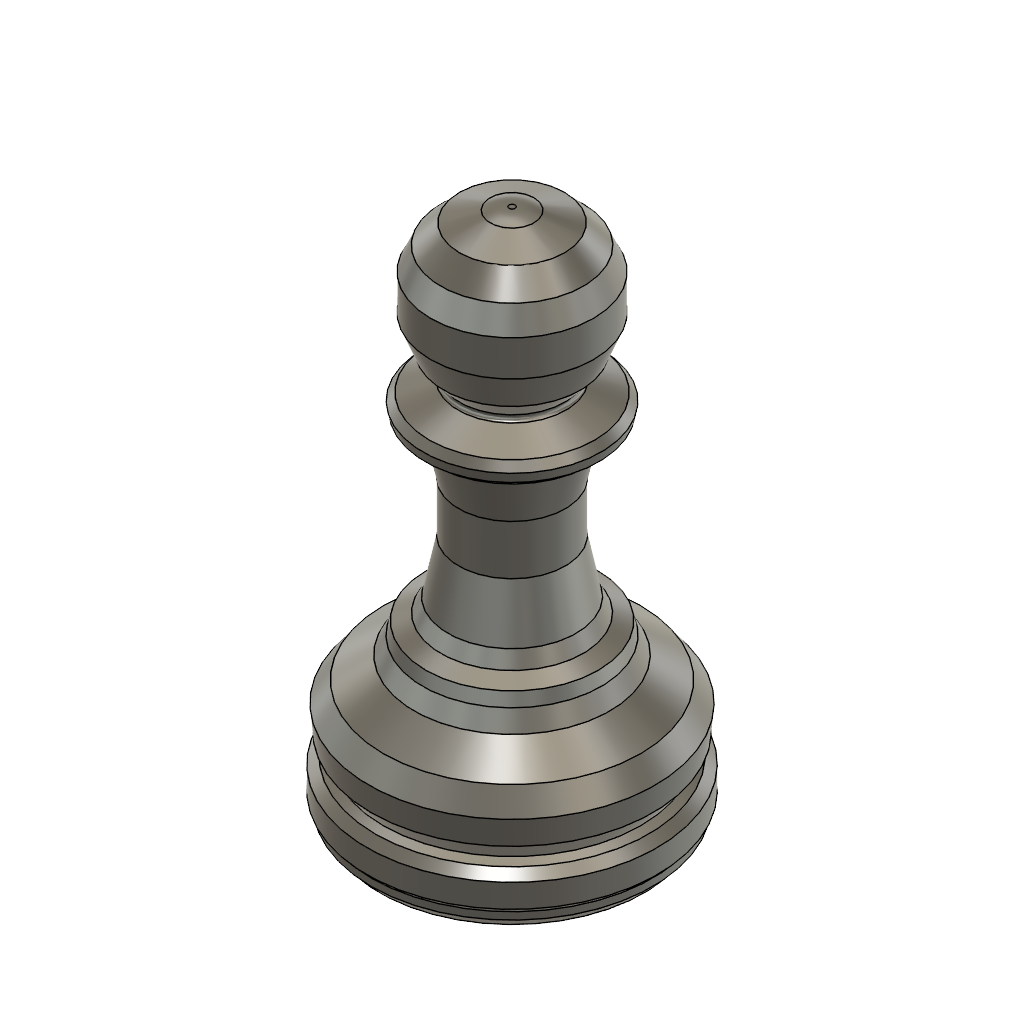
Board Assembly (Autodesk Fusion 360 archive; units mm, degrees)
design "Simple Pawn"
part number: 2026-10-13-13-34-46-267
Autodesk Fusion 360 part; units mm, degrees
sketch "Sketch1" plane through (0, 0, 0) normal (1, 0, 0) x (0, 0, -1)
  line L0 (-0.0053, -17.729) -> (1.2282, -17.729)
  line L1 (1.2282, -17.729) -> (5, -17.5)
  line L2 (5, -17.5) -> (7.3961, -17.1698)
  line L3 (7.3961, -17.1698) -> (8.684, -16.9923)
  line L4 (8.684, -16.9923) -> (9.2382, -16.3474)
  line L5 (9.2382, -16.3474) -> (9.2382, -15.8704)
  line L6 (9.2382, -15.8704) -> (9.5278, -15.5336)
  line L7 (9.5278, -15.5336) -> (9.5278, -14)
  line L8 (9.5278, -14) -> (8.9611, -13.5131)
  line L9 (8.9611, -13.5131) -> (8.4323, -13.3046)
  line L10 (8.4323, -13.3046) -> (9.2444, -12.1533)
  line L11 (9.2444, -12.1533) -> (9.383, -10.525)
  line L12 (9.383, -10.525) -> (8.4323, -9.2091)
  line L13 (8.4323, -9.2091) -> (7.1598, -8.3116)
  line L14 (7.1598, -8.3116) -> (6.4164, -7.7872)
  line L15 (6.4164, -7.7872) -> (5.85, -6.6762)
  line L16 (5.85, -6.6762) -> (5.6527, -5.8538)
  line L17 (5.6527, -5.8538) -> (4.6658, -5.3933)
  line L18 (4.6658, -5.3933) -> (4.2015, -4.4825)
  line L19 (4.2015, -4.4825) -> (3.5, -1)
  line L20 (3.5, -1) -> (3.5, 2.2549)
  line L21 (3.5, 2.2549) -> (4.2015, 5.5608)
  line L22 (4.2015, 5.5608) -> (5.1592, 5.5608)
  line L23 (5.1592, 5.5608) -> (5.7184, 6.0378)
  line L24 (5.7184, 6.0378) -> (5.8486, 6.6512)
  line L25 (5.8486, 6.6512) -> (5.4388, 7.1316)
  line L26 (5.4388, 7.1316) -> (4.5, 7.5)
  line L27 (4.5, 7.5) -> (3.7306, 7.8019)
  line L28 (3.7306, 7.8019) -> (3.2099, 8.0063)
  line L29 (3.2099, 8.0063) -> (4.5, 9.5)
  line L30 (4.5, 9.5) -> (5.3466, 11.6575)
  line L31 (5.3466, 11.6575) -> (5.3466, 14)
  line L32 (5.3466, 14) -> (4.6822, 15.4952)
  line L33 (4.6822, 15.4952) -> (3.4487, 16.7781)
  line L34 (3.4487, 16.7781) -> (0.8335, 17.6828)
  line L35 (0.8335, 17.6828) -> (0, 17.6828)
  line L36 (-0.0053, -17.729) -> (0, 17.6828)
  constraint horizontal L0
  constraint parallel L2 L3
  constraint vertical L5
  constraint parallel L4 L6
  constraint parallel L5 L7
  constraint perpendicular L6 L8
  constraint perpendicular L10 L13
  constraint perpendicular L10 L14
  constraint parallel L15 L18
  constraint vertical L20
  constraint perpendicular L20 L22
  constraint parallel L21 L24
  constraint perpendicular L23 L25
  constraint parallel L26 L27
  constraint perpendicular L28 L30
  constraint vertical L31
  constraint horizontal L35
revolve "Revolve1" add sketch "Sketch1" angle 360 about axis through (0, -17.729, 0.0053) along (0, 1, -0.000151)
move_body "Move1" bodies 1 to x (1, 0, 0) y (0, 1, 0) z (0, 0, 1) at (0, 0, -28)
sketch "Sketch2" plane through (0, 0, 0) normal (0, 0, 1) x (1, 0, 0)
  line L0 (-8.7, -17) -> (8.5, -17)
  line L1 (8.5, -17) -> (8.5, -18)
  line L2 (8.5, -18) -> (-8.7, -18)
  line L3 (-8.7, -18) -> (-8.7, -17)
  constraint horizontal L0
  constraint vertical L1
  constraint horizontal L2
  constraint vertical L3
extrude "Extrude1" cut sketch "Sketch2" against normal blind 39
fillet "Fillet1" radius 0.25 1 edges at (-2.994, 8.0066, -29.1598)
fillet "Fillet2" radius 3.8 1 edges at (-0.7771, 17.6828, -28.3014)
sketch "Sketch3" plane through (0, -17, 0) normal (0, -1, 0) x (1, 0, 0)
  ellipse E0 centre (0, -28.0042) end of major axis (0, -36.6284) minor radius 8.6242 (8.5, -26.5458) -> (8.5, -29.4626) ccw
  line L0 (8.5, -29.4626) -> (8.5, -26.5458)
  circle A0 centre (0, -28.0042) radius 3.15
  dimension "d8" = 6.3
  constraint concentric E0 A0
  measures "d8" diameter of A0
extrude "Extrude2" cut sketch "Sketch3" against normal blind 2.2 contours A0

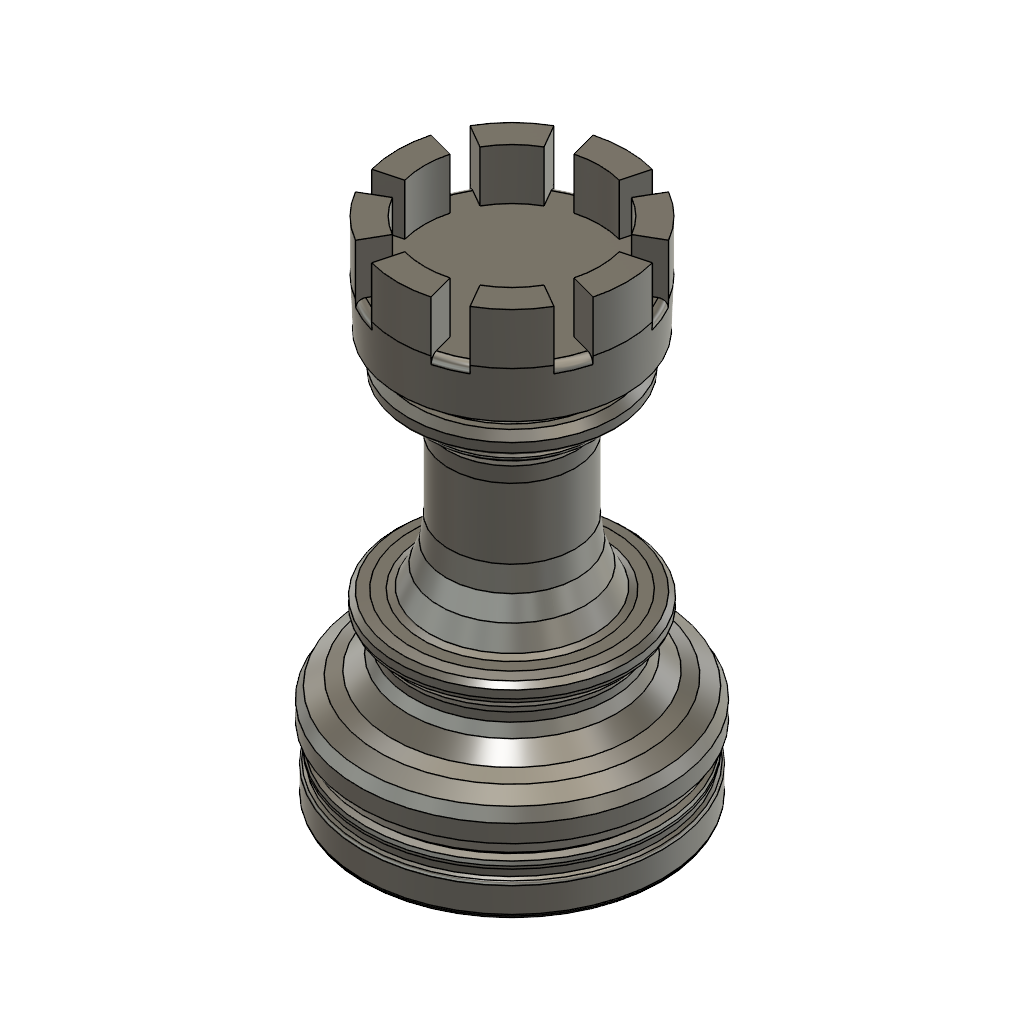
design "Tower"
part number: 2026-10-13-14-45-00-244
Autodesk Fusion 360 part; units mm, degrees
sketch "Sketch1" plane through (0, 0, 0) normal (0, 0, 1) x (1, 0, 0)
  line L0 (0, -18.1) -> (2.1, -18.1)
  line L1 (2.1, -18.1) -> (5.6, -17.9)
  line L2 (5.6, -17.9) -> (8.5, -17.4)
  line L3 (8.5, -17.4) -> (10.2, -16.7)
  line L4 (10.2, -16.7) -> (10.3, -16.5)
  line L5 (10.3, -16.5) -> (10.3, -14.6)
  line L6 (10.3, -14.6) -> (10, -14.4)
  line L7 (10, -14.4) -> (10.15, -13.7818)
  line L8 (10.15, -13.7818) -> (10.075, -13.4284)
  line L9 (10.075, -13.4284) -> (9.6033, -13.3139)
  line L10 (9.6033, -13.3139) -> (9.9799, -12.9804)
  line L11 (9.9799, -12.9804) -> (10.5, -12.1)
  line L12 (10.5, -12.1) -> (10.5, -10.9)
  line L13 (10.5, -10.9) -> (10.1125, -10.1526)
  line L14 (10.1125, -10.1526) -> (9.1034, -9.5566)
  line L15 (9.1034, -9.5566) -> (8.2, -9.2)
  line L16 (8.2, -9.2) -> (7.6575, -8.7025)
  line L17 (7.6575, -8.7025) -> (7.1474, -8.2346)
  line L18 (7.1474, -8.2346) -> (6.8, -7.5)
  line L19 (6.8, -7.5) -> (6.8, -6.9)
  line L20 (6.8, -6.9) -> (7.1474, -6.3425)
  line L21 (7.1474, -6.3425) -> (7.8026, -5.6281)
  line L22 (7.8026, -5.6281) -> (7.9288, -5.3339)
  line L23 (7.9288, -5.3339) -> (7.9288, -4.8)
  line L24 (7.9288, -4.8) -> (7.5936, -4.4926)
  line L25 (7.5936, -4.4926) -> (6.9, -4.4)
  line L26 (6.9, -4.4) -> (6.1, -4.4)
  line L27 (6.1, -4.4) -> (5.6617, -4.2347)
  line L28 (5.6617, -4.2347) -> (5, -2.9)
  line L29 (5, -2.9) -> (4.5, -1.5)
  line L30 (4.5, -1.5) -> (4.3, 0.1)
  line L31 (4.3, 0.1) -> (4.3, 2.7)
  line L32 (4.3, 2.7) -> (4.3, 4.9)
  line L33 (4.3, 4.9) -> (4.4, 6)
  line L34 (4.4, 6) -> (5.1, 6.8)
  line L35 (5.1, 6.8) -> (5.6, 7.2)
  line L36 (5.6, 7.2) -> (5.4101, 7.4374)
  line L37 (5.4101, 7.4374) -> (5.4101, 7.8)
  line L38 (5.4101, 7.8) -> (6.4, 8.4)
  line L39 (6.4, 8.4) -> (7, 8.4)
  line L40 (7, 8.4) -> (7.1, 9.3)
  line L41 (7.1, 9.3) -> (6.7, 9.8)
  line L42 (0, 9.9896) -> (0, -18.1)
  line L43 (6.7, 9.8) -> (6.2466, 9.8)
  line L44 (6.2466, 9.8) -> (7.5109, 10.8114)
  line L45 (7.5109, 10.8114) -> (7.7356, 10.9912)
  line L46 (7.7356, 10.9912) -> (7.8539, 14.2278)
  line L47 (7.8539, 14.2278) -> (0, 14.2278)
  line L48 (0, 14.2278) -> (0, 9.9896)
  constraint horizontal L0
  constraint vertical L5
  constraint perpendicular L7 L9
  constraint vertical L12
  constraint perpendicular L11 L14
  constraint parallel L16 L17
  constraint vertical L19
  constraint perpendicular L16 L21
  constraint parallel L19 L23
  constraint perpendicular L21 L24
  constraint perpendicular L23 L26
  constraint vertical L31
  constraint parallel L31 L32
  constraint vertical L37
  constraint horizontal L39
  constraint perpendicular L0 L42
  constraint horizontal L43
  constraint perpendicular L41 L44
  constraint perpendicular L41 L45
  constraint horizontal L47
  constraint perpendicular L47 L48
revolve "Revolve1" add sketch "Sketch1" angle 360 about axis through (0, 9.9896, 0) along (0, -1, 0)
sketch "Sketch2" plane through (0, 14.2278, 0) normal (0, 1, 0) x (-1, 0, 0)
  circle A0 centre (0, 0) radius 7.8539
  circle A1 centre (0, 0) radius 6
  line L0 (0, 0) -> (-2.0327, -7.5863)
  line L1 (0, 0) -> (2.0327, -7.5863)
  line L2 (0, 0) -> (0, -5.5)
  line L3 (0, -5.5) -> (0, -6)
  line L4 (0, 0) -> (3.927, -6.8017)
  line L5 (0, 0) -> (6.8017, -3.927)
  line L6 (0, 0) -> (7.5863, -2.0327)
  line L7 (0, 0) -> (7.5863, 2.0327)
  line L8 (0, 0) -> (6.8017, 3.927)
  line L9 (0, 0) -> (3.927, 6.8017)
  line L10 (0, 0) -> (2.0327, 7.5863)
  line L11 (0, 0) -> (-2.0327, 7.5863)
  line L12 (0, 0) -> (-3.927, 6.8017)
  line L13 (0, 0) -> (-6.8017, 3.927)
  line L14 (0, 0) -> (-7.5863, 2.0327)
  line L15 (0, 0) -> (-7.5863, -2.0327)
  line L16 (0, 0) -> (-6.8017, -3.927)
  line L17 (0, 0) -> (-3.927, -6.8017)
  dimension "d2" = 12
  dimension "d4" = 15
  dimension "d5" = 15
  dimension "d7" = 360
  constraint concentric A0 A1
  constraint coincident A0.centre A1.centre
  constraint coincident A0 L0.end
  constraint coincident A0 L1.end
  constraint vertical L2
  constraint coincident A1 L3.end
  constraint perpendicular A1 L3
  measures "d2" diameter of A1
  measures "d4" angle of L0 L3
  measures "d5" angle of L1 L2
extrude "Extrude1" add sketch "Sketch2" along normal blind 3.5 contours A0 A1 L6 L7 | A0 A1 L8 L9 | A0 A1 L4 L5 | A0 A1 L10 L11 | A0 A1 L0 L1 | A0 A1 L12 L13 | A0 A1 L14 L15 | A0 A1 L16 L17
fillet "Fillet1" radius 0.5 tangency weight 0.99014 8 edges at (-3.0056, 14.2278, 7.2561) (-7.2561, 14.2278, 3.0056) (-7.2561, 14.2278, -3.0056) (-3.0056, 14.2278, -7.2561) (3.0056, 14.2278, -7.2561) (7.2561, 14.2278, -3.0056) (7.2561, 14.2278, 3.0056) (3.0056, 14.2278, 7.2561)
fillet "Fillet2" radius 0.1 1 edges at (-5.221, 7.2, -2.025)
fillet "Fillet3" radius 0.25 1 edges at (-6.5263, 8.4, -2.5313)
fillet "Fillet4" radius 0.25 2 edges at (-9.603, -16.5, -3.7246) (-9.603, -14.6, -3.7246)
fillet "Fillet5" radius 0.4 1 edges at (-9.4631, -13.7818, -3.6704)
sketch "Sketch3" plane through (0, 0, 0) normal (0, 0, 1) x (1, 0, 0)
  line L0 (-8.5, -17.4) -> (9.5169, -17.4)
  line L1 (9.5169, -17.4) -> (9.5169, -18.8567)
  line L2 (9.5169, -18.8567) -> (-8.5, -18.8567)
  line L3 (-8.5, -18.8567) -> (-8.5, -17.4)
  constraint horizontal L0
  constraint vertical L1
  constraint horizontal L2
  constraint vertical L3
extrude "Extrude2" cut sketch "Sketch3" along normal blind 19 and the other way blind 40.5
scale "Scale1" factors (1.1, 1.1, 1.1) about (4.3, 0.1, 0) bodies 1
sketch "Sketch4" plane through (0, -19.15, 0) normal (0, -1, 0) x (1, 0, 0)
  circle A0 centre (-0.43, 0) radius 9.35
  circle A1 centre (-0.43, 0) radius 3.15
  dimension "d27" = 6.3
  constraint concentric A0 A1
  measures "d27" diameter of A1
extrude "Extrude3" cut sketch "Sketch4" against normal blind 2.2 contours A1

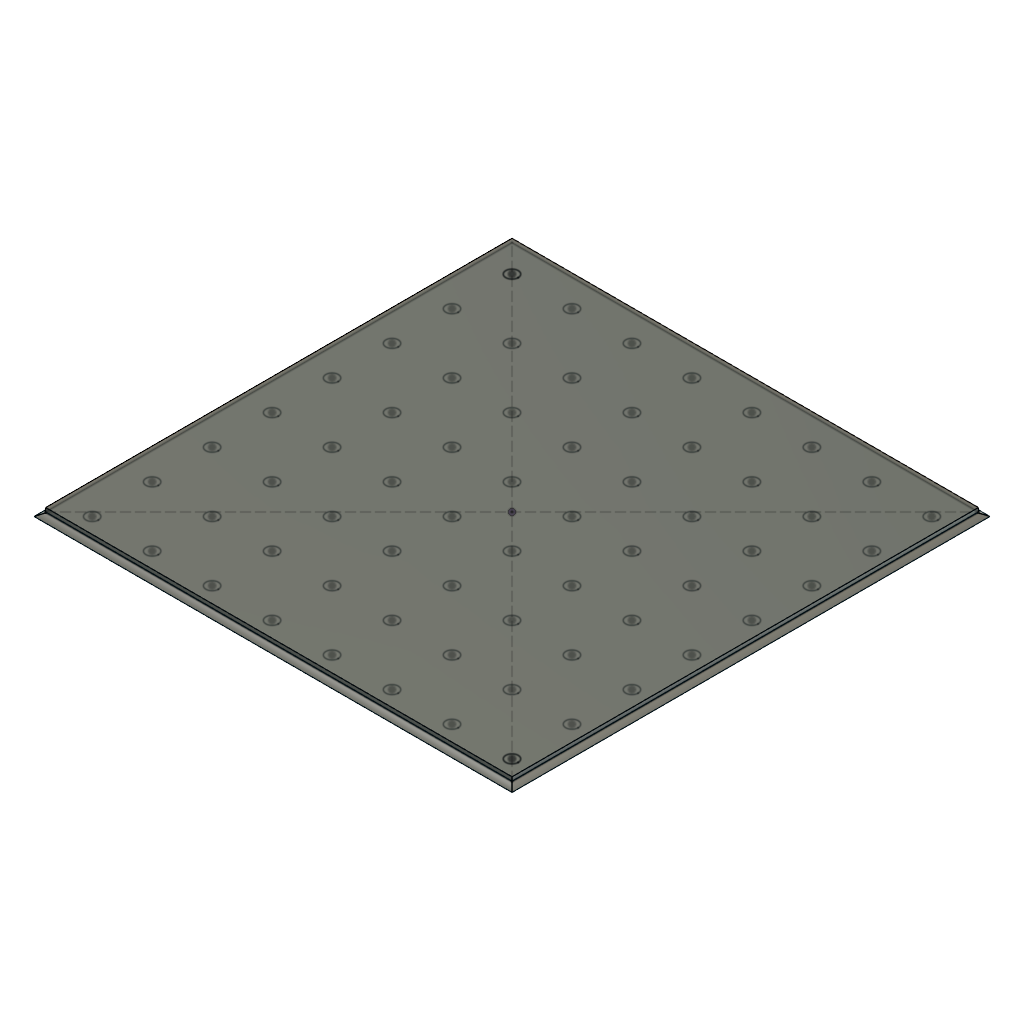
design "Board"
part number: 2026-10-15-21-07-23-463
part number: 2026-10-15-21-11-25-391
Autodesk Fusion 360 part; units mm, degrees
sketch "Sketch1" plane through (0, 0, 0) normal (0, 1, 0) x (1, 0, 0)
  line L0 (120, -120) -> (-120, -120)
  line L1 (-120, -120) -> (-120, 120)
  line L2 (-120, 120) -> (120, 120)
  line L3 (120, 120) -> (120, -120)
  line L4 (120, -120) -> (-120, 120) construction
  line L5 (-120, -120) -> (120, 120) construction
  dimension "d1" = 240
  dimension "d2" = 240
  constraint horizontal L0
  constraint perpendicular L0 L1
  constraint parallel L0 L2
  constraint parallel L1 L3
  constraint coincident L4 origin
  constraint coincident L5 origin
  measures "d1" distance of L1.end L2.end
  measures "d2" distance of L0.end L1.end
extrude "Extrude2" add sketch "Sketch1" along normal blind 2 makes body 1
sketch "Sketch2" plane through (0, 0, 0) normal (0, -1, 0) x (1, 0, 0)
  line L0 (-120, -120) -> (120, -120) construction
  line L1 (120, -120) -> (120, 120) construction
  line L2 (120, 120) -> (-120, 120) construction
  line L3 (-120, 120) -> (-120, -120) construction
  line L4 (-123, 123) -> (-123, -123)
  line L5 (-123, -123) -> (123, -123)
  line L6 (123, -123) -> (123, 123)
  line L7 (123, 123) -> (-123, 123)
  dimension "d5" = 3
extrude "Extrude2'" add sketch "Sketch2" along normal blind 2 makes body 2 in component "Component"
fillet "Fillet1" radius 10 4 edges at (0, 0, 123) (-123, 0, 0) (0, 0, -123) (123, 0, 0) on bodies 2 in component "Component"
sketch "Sketch3" plane through (0, -2, 0) normal (0, -1, 0) x (1, 0, 0)
  line L0 (123, 123) -> (-123, 123)
  line L1 (-123, 123) -> (-123, -123)
  line L2 (-123, -123) -> (123, -123)
  line L3 (123, -123) -> (123, 123)
  circle A0 centre (-108, 108) radius 3.15
  circle A1 centre (108, 108) radius 3.15
  circle A2 centre (-108, -108) radius 3.15
  circle A3 centre (-77.1429, 108) radius 3.15
  circle A4 centre (-46.2857, 108) radius 3.15
  circle A5 centre (-15.4286, 108) radius 3.15
  circle A6 centre (15.4286, 108) radius 3.15
  circle A7 centre (46.2857, 108) radius 3.15
  circle A8 centre (77.1429, 108) radius 3.15
  circle A9 centre (108, 108) radius 3.15
  circle A10 centre (-108, 77.1429) radius 3.15
  circle A11 centre (-77.1429, 77.1429) radius 3.15
  circle A12 centre (-46.2857, 77.1429) radius 3.15
  circle A13 centre (-15.4286, 77.1429) radius 3.15
  circle A14 centre (15.4286, 77.1429) radius 3.15
  circle A15 centre (46.2857, 77.1429) radius 3.15
  circle A16 centre (77.1429, 77.1429) radius 3.15
  circle A17 centre (108, 77.1429) radius 3.15
  circle A18 centre (-108, 46.2857) radius 3.15
  circle A19 centre (-77.1429, 46.2857) radius 3.15
  circle A20 centre (-46.2857, 46.2857) radius 3.15
  circle A21 centre (-15.4286, 46.2857) radius 3.15
  circle A22 centre (15.4286, 46.2857) radius 3.15
  circle A23 centre (46.2857, 46.2857) radius 3.15
  circle A24 centre (77.1429, 46.2857) radius 3.15
  circle A25 centre (108, 46.2857) radius 3.15
  circle A26 centre (-108, 15.4286) radius 3.15
  circle A27 centre (-77.1429, 15.4286) radius 3.15
  circle A28 centre (-46.2857, 15.4286) radius 3.15
  circle A29 centre (-15.4286, 15.4286) radius 3.15
  circle A30 centre (15.4286, 15.4286) radius 3.15
  circle A31 centre (46.2857, 15.4286) radius 3.15
  circle A32 centre (77.1429, 15.4286) radius 3.15
  circle A33 centre (108, 15.4286) radius 3.15
  circle A34 centre (-108, -15.4286) radius 3.15
  circle A35 centre (-77.1429, -15.4286) radius 3.15
  circle A36 centre (-46.2857, -15.4286) radius 3.15
  circle A37 centre (-15.4286, -15.4286) radius 3.15
  circle A38 centre (15.4286, -15.4286) radius 3.15
  circle A39 centre (46.2857, -15.4286) radius 3.15
  circle A40 centre (77.1429, -15.4286) radius 3.15
  circle A41 centre (108, -15.4286) radius 3.15
  circle A42 centre (-108, -46.2857) radius 3.15
  circle A43 centre (-77.1429, -46.2857) radius 3.15
  circle A44 centre (-46.2857, -46.2857) radius 3.15
  circle A45 centre (-15.4286, -46.2857) radius 3.15
  circle A46 centre (15.4286, -46.2857) radius 3.15
  circle A47 centre (46.2857, -46.2857) radius 3.15
  circle A48 centre (77.1429, -46.2857) radius 3.15
  circle A49 centre (108, -46.2857) radius 3.15
  circle A50 centre (-108, -77.1429) radius 3.15
  circle A51 centre (-77.1429, -77.1429) radius 3.15
  circle A52 centre (-46.2857, -77.1429) radius 3.15
  circle A53 centre (-15.4286, -77.1429) radius 3.15
  circle A54 centre (15.4286, -77.1429) radius 3.15
  circle A55 centre (46.2857, -77.1429) radius 3.15
  circle A56 centre (77.1429, -77.1429) radius 3.15
  circle A57 centre (108, -77.1429) radius 3.15
  circle A58 centre (-108, -108) radius 3.15
  circle A59 centre (-77.1429, -108) radius 3.15
  circle A60 centre (-46.2857, -108) radius 3.15
  circle A61 centre (-15.4286, -108) radius 3.15
  circle A62 centre (15.4286, -108) radius 3.15
  circle A63 centre (46.2857, -108) radius 3.15
  circle A64 centre (77.1429, -108) radius 3.15
  circle A65 centre (108, -108) radius 3.15
  dimension "d10" = 6.3
  dimension "d13" = 15
  dimension "d14" = 15
  dimension "d15" = 6.3
  dimension "d16" = 15
  dimension "d17" = 15
  dimension "d18" = 6.3
  dimension "d19" = 15
  dimension "d20" = 15
  dimension "d23" = 216
  dimension "d24" = -216
  measures "d10" diameter of A0
  measures "d13" distance of L1 A0.centre
  measures "d14" distance of L0 A0.centre
  measures "d15" diameter of A1
  measures "d16" distance of L3 A1.centre
  measures "d17" distance of L0 A1.centre
  measures "d18" diameter of A2
  measures "d19" distance of L2 A2.centre
  measures "d20" distance of L1 A2.centre
extrude "Extrude3" cut sketch "Sketch3" against normal blind 2.2 contours A0 bodies 2 in component "Component"
extrude "Extrude4" cut sketch "Sketch3" against normal blind 2.2 contours A0 | A1 A9 | A3 | A4 | A5 | A6 | A7 | A8 bodies 2 in component "Component"
extrude "Extrude5" cut sketch "Sketch3" against normal blind 2.2 contours A10 | A11 | A12 | A13 | A14 | A15 | A16 | A17 bodies 2 in component "Component"
extrude "Extrude6" cut sketch "Sketch3" against normal blind 2.2 contours A18 | A19 | A20 | A21 | A22 | A23 | A24 | A25 bodies 2 in component "Component"
extrude "Extrude7" cut sketch "Sketch3" against normal blind 2.2 contours A26 | A27 | A28 | A29 | A30 | A31 | A32 | A33 bodies 2 in component "Component"
extrude "Extrude8" cut sketch "Sketch3" against normal blind 2.2 contours A34 | A35 | A36 | A37 | A38 | A39 | A40 | A41 bodies 2 in component "Component"
extrude "Extrude9" cut sketch "Sketch3" against normal blind 2.2 contours A42 | A43 | A44 | A45 | A46 | A47 | A48 | A49 bodies 2 in component "Component"
extrude "Extrude10" cut sketch "Sketch3" against normal blind 2.2 contours A50 | A51 | A52 | A53 | A54 | A55 | A56 | A57 bodies 2 in component "Component"
extrude "Extrude3'" cut sketch "Sketch3" against normal blind 2.2 contours A2 A58 | A59 | A60 | A61 | A62 | A63 | A64 | A65 bodies 1
extrude "Extrude12" cut sketch "Sketch3" against normal blind 2.2 contours A2 A58 | A59 | A60 | A61 | A62 | A63 | A64 | A65 bodies 2 in component "Component"
extrude "Extrude11" [rolled back] along distance -2.2 taper angle 0 in component "Component"
component "Component" placed x (1, 0, 0) y (0, 1, 0) z (0, 0, 1) at (0, 0, 0)

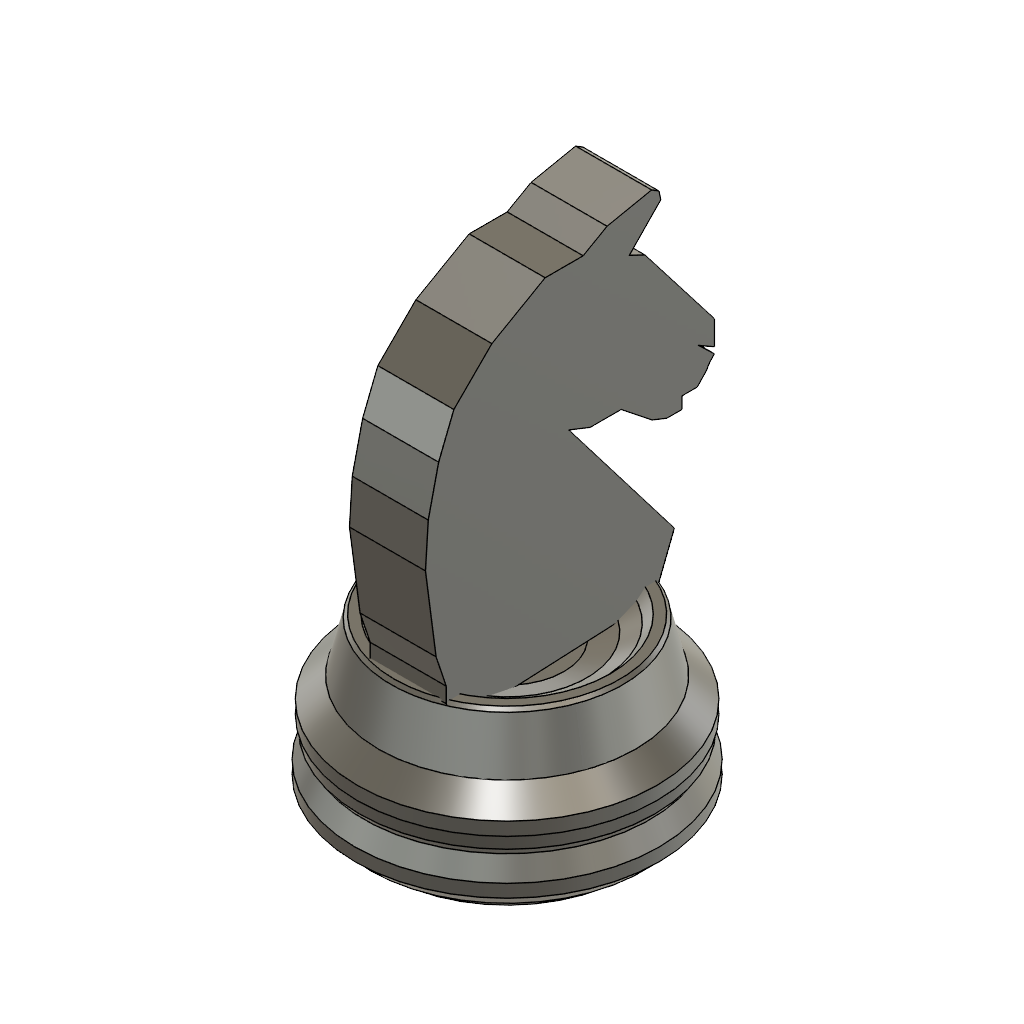
design "Horse"
part number: 2026-10-14-15-19-01-770
Autodesk Fusion 360 part; units mm, degrees
sketch "Sketch1" plane through (0, 0, 0) normal (1, 0, 0) x (0, 0, -1)
  line L0 (0, -17.5) -> (2.7905, -17.1997)
  line L1 (2.7905, -17.1997) -> (5.5, -16.5)
  line L2 (5.5, -16.5) -> (7.9291, -15.3606)
  line L3 (7.9291, -15.3606) -> (9, -14.5)
  line L4 (9, -14.5) -> (10, -13.5)
  line L5 (10, -13.5) -> (10, -12.6561)
  line L6 (10, -12.6561) -> (9.7013, -12.0194)
  line L7 (9.7013, -12.0194) -> (9.4046, -11.3868)
  line L8 (9.4046, -11.3868) -> (9.7013, -10.9252)
  line L9 (9.7013, -10.9252) -> (9.8507, -10.0868)
  line L10 (9.8507, -10.0868) -> (9.8507, -9.2214)
  line L11 (9.8507, -9.2214) -> (9.2003, -8.5993)
  line L12 (9.2003, -8.5993) -> (8.4409, -7.8731)
  line L13 (8.4409, -7.8731) -> (8.2672, -7.1795)
  line L14 (8.2672, -7.1795) -> (8.0608, -6.3555)
  line L15 (8.0608, -6.3555) -> (7.8831, -5.646)
  line L16 (7.8831, -5.646) -> (7.6911, -4.8793)
  line L17 (7.6911, -4.8793) -> (7.6218, -4.6025)
  line L18 (7.6218, -4.6025) -> (7.4153, -4.3938)
  line L19 (7.4153, -4.3938) -> (6.7932, -4.3938)
  line L20 (6.7932, -4.3938) -> (6.2833, -4.8985)
  line L21 (6.2833, -4.8985) -> (5.2381, -5.408)
  line L22 (5.2381, -5.408) -> (3.7371, -5.8001)
  line L23 (3.7371, -5.8001) -> (0.7081, -6.0571)
  line L24 (0.7081, -6.0571) -> (2.2226, -5.9286)
  line L25 (0.0385, -6.0571) -> (0.7081, -6.0571)
  line L26 (0.0385, -6.0571) -> (0, -17.5)
  line L27 (-7, -4) -> (-7.5, -2.5)
  line L28 (-7.5, -2.5) -> (-7.5, -1.5)
  line L29 (-7.5, -1.5) -> (-8.1672, 0.5015)
  line L30 (-8.1672, 0.5015) -> (-8.5, 3)
  line L31 (-8.5, 3) -> (-8.8653, 5.742)
  line L32 (-8.8653, 5.742) -> (-8.6826, 8.5466)
  line L33 (-8.6826, 8.5466) -> (-8, 11.5)
  line L34 (-8, 11.5) -> (-7, 14)
  line L35 (-7, 14) -> (-4.5, 16.5)
  line L36 (-4.5, 16.5) -> (-1, 18.5)
  line L37 (-1, 18.5) -> (1.5, 18.5)
  line L38 (1.5, 18.5) -> (3.07, 19.3972)
  line L39 (3.07, 19.3972) -> (6, 20)
  line L40 (6, 20) -> (4.535, 19.6986)
  line L41 (6, 20) -> (6.4862, 19.6986)
  line L42 (6.4862, 19.6986) -> (6.6024, 19.1337)
  line L43 (6.6024, 19.1337) -> (4.535, 17.0095)
  line L44 (4.535, 17.0095) -> (5.5687, 16.5153)
  line L45 (5.5687, 16.5153) -> (7.712, 13.7408)
  line L46 (7.712, 13.7408) -> (8.7552, 12.3903)
  line L47 (8.7552, 12.3903) -> (10.1338, 10.6057)
  line L48 (10.1338, 10.6057) -> (10.1338, 9.7512)
  line L49 (10.1338, 9.7512) -> (10.1338, 9)
  line L50 (10.1338, 9) -> (9.4821, 9.3756)
  line L51 (9.4821, 9.3756) -> (9.078, 9.6086)
  line L52 (9.078, 9.6086) -> (10.1338, 8.6084)
  line L53 (10.1338, 8.6084) -> (9.808, 8.2645)
  line L54 (9.808, 8.2645) -> (9.6059, 7.9139)
  line L55 (9.6059, 7.9139) -> (9.0005, 7.2749)
  line L56 (9.0005, 7.2749) -> (8, 7.2749)
  line L57 (8, 7.2749) -> (8, 6.5)
  line L58 (8, 6.5) -> (7, 6.5)
  line L59 (7, 6.5) -> (6.0229, 6.8874)
  line L60 (6.0229, 6.8874) -> (4, 8.5)
  line L61 (4, 8.5) -> (1.956, 8.5)
  line L62 (1.956, 8.5) -> (0.8278, 8.9474)
  line L63 (0.8278, 8.9474) -> (0.566, 9.0512)
  line L64 (0.566, 9.0512) -> (7.5, 0)
  line L65 (7.5, 0) -> (6.1637, -3.3701)
  line L66 (6.1637, -3.3701) -> (-7, -4)
  constraint vertical L5
  constraint perpendicular L2 L6
  constraint parallel L6 L7
  constraint vertical L10
  constraint parallel L11 L12
  constraint parallel L13 L14
  constraint parallel L14 L15
  constraint parallel L15 L16
  constraint parallel L16 L17
  constraint horizontal L19
  constraint perpendicular L18 L20
  constraint parallel L23 L24
  constraint horizontal L25
  constraint vertical L28
  constraint parallel L27 L29
  constraint parallel L30 L31
  constraint horizontal L37
  constraint parallel L36 L38
  constraint parallel L39 L40
  constraint perpendicular L40 L42
  constraint parallel L45 L46
  constraint parallel L46 L47
  constraint vertical L48
  constraint parallel L48 L49
  constraint parallel L50 L51
  constraint perpendicular L52 L53
  constraint perpendicular L50 L54
  constraint perpendicular L52 L55
  constraint horizontal L56
  constraint perpendicular L56 L57
  constraint perpendicular L57 L58
  constraint parallel L58 L61
  constraint perpendicular L63 L65
revolve "Revolve1" add sketch "Sketch1" angle 360 about axis through (0, 1.75, 0) along (0, 1, 0) contours L0 L1 L2 L3 L4 L5 L6 L7 L8 L9 L10 L11 L12 L13 L14 L15 L16 L17 L18 L19 L20 L21 L22 L23 L24 L25 L26 makes body 1
sketch "Sketch2" plane through (0, 0, 0) normal (1, 0, 0) x (0, 0, -1)
  line L0 (-8, -15.5) -> (8, -15.5)
  line L1 (8, -15.5) -> (8, -18.5)
  line L2 (8, -18.5) -> (-8, -18.5)
  line L3 (-8, -18.5) -> (-8, -15.5)
  constraint horizontal L0
  constraint vertical L1
  constraint horizontal L2
  constraint vertical L3
extrude "Extrude2" cut sketch "Sketch2" along normal blind -10.5 and the other way blind -10 bodies 1
extrude "Extrude1" add sketch "Sketch1" along normal blind 5 separate body contours L27 L28 L29 L30 L31 L32 L33 L34 L35 L36 L37 L38 L39 L40 L41 L42 L43 L44 L45 L46 L47 L48 L49 L50 L51 L52 L53 L54 L55 L56 L57 L58 L59 L60 L61 L62 L63 L64 L65 L66 makes body 2
move_body "Move1" bodies 2 to x (1, 0, 0) y (0, 1, 0) z (0, 0, 1) at (-2, -2, 0)
move_body "Move2" bodies 2 to x (1, 0, 0) y (0, 1, 0) z (0, 0, 1) at (0, 0, -0.5)
sketch "Sketch3" plane through (0, -15.5, 0) normal (0, -1, 0) x (1, 0, 0)
  circle A0 centre (0, 0) radius 7.632
  circle A1 centre (0, 0) radius 0.0067
  circle A2 centre (0, 0) radius 3.15
  dimension "d29" = 6.3
  constraint coincident A0.centre A1.centre
  measures "d29" diameter of A2
extrude "Extrude4" cut sketch "Sketch3" against normal blind 2.2 contours A2 bodies 1
fillet "Fillet1" [rolled back] radius 2
fillet "Fillet2" [rolled back] radius 2
fillet "Fillet3" [rolled back] radius 0.65
fillet "Fillet4" [rolled back] radius 0.35
fillet "Fillet5" [rolled back] radius 0.25
fillet "Fillet6" [rolled back] radius 1
extrude "Extrude3" [rolled back] along distance 1 taper angle 0
fillet "Fillet7" [rolled back] radius 0.25
fillet "Fillet8" [rolled back] radius 1.75
scale "Scale1" [rolled back] scale x 1.1 scale y 1.15 scale z 1.1
